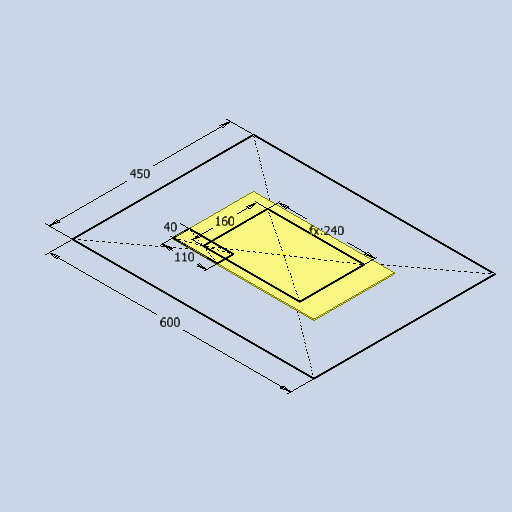
# Autodesk Inventor part: CHASSIS PLATE
Saved by Autodesk Inventor 2026.3 (Build 303398000, 398)
## iProperties
Created: 2026-10-19
Part Number: CHASSIS PLATE
Material: G11 Glass Epoxy Laminate
Document SubType Name: Modeling
Designer: Salim
Density: 18.4985 g/cm^3
Appearance: FIBER
Mass: 3884.68 g
Surface Area: 1433 cm^2
Volume: 210 cm^3
Author: Salim
Autodesk Inventor part; units mm, degrees
ref_plane "YZ Plane" through (0, 0, 0) normal (1, 0, 0) x (0, 1, 0)
ref_plane "XZ Plane" through (0, 0, 0) normal (0, 1, 0) x (-1, 0, 0)
ref_plane "XY Plane" through (0, 0, 0) normal (0, 0, 1) x (1, 0, 0)
sketch "Sketch1" plane through (0, 0, 0) normal (0, 1, 0) x (-1, 0, 0)
  line L0 (-300, -225) -> (300, -225)
  line L1 (300, -225) -> (300, 225)
  line L2 (300, 225) -> (-300, 225)
  line L3 (-300, 225) -> (-300, -225)
  line L4 (-300, -225) -> (300, 225) construction
  line L5 (300, -225) -> (-300, 225) construction
  point P0 (0, 0)
  dimension "d0" = 600
  dimension "d1" = 450
  constraints: 12 end point, 2 midpoint, 2 parallel, 1 horizontal, 1 perpendicular
  measures "d0" distance of L2.end L1.end
  measures "d1" distance of L1.end L0.end
sketch "Sketch2" plane through (0, 0, 0) normal (0, 1, 0) x (-1, 0, 0)
  line L0 (-175, -100) -> (175, -100)
  line L1 (175, -100) -> (175, 100)
  line L2 (175, 100) -> (-175, 100)
  line L3 (-175, 100) -> (-175, -100)
  line L4 (-175, -100) -> (175, 100) construction
  line L5 (175, -100) -> (-175, 100) construction
  point P0 (0, 0)
  dimension "d4" = 350
  dimension "d5" = 200
  constraints: 12 end point, 2 midpoint, 2 parallel, 1 horizontal, 1 perpendicular
  measures "d4" distance of L2.end L1.end
  measures "d5" distance of L1.end L0.end
extrude "Extrusion1" add sketch "Sketch2" along normal blind 3
sketch "Sketch3" plane through (0, 3, 0) normal (0, 1, 0) x (1, 0, 0)
  line L0 (120, -80) -> (-120, -80)
  line L1 (-120, -80) -> (-120, 80)
  line L2 (-120, 80) -> (120, 80)
  line L3 (120, 80) -> (120, -80)
  line L4 (120, -80) -> (-120, 80) construction
  line L5 (-120, -80) -> (120, 80) construction
  line L6 (-65, -60) -> (-175, -60)
  line L7 (-175, -60) -> (-175, -100)
  line L8 (-175, -100) -> (-65, -100)
  line L9 (-65, -100) -> (-65, -60)
  line L10 (-65, -60) -> (-175, -100) construction
  line L11 (-175, -60) -> (-65, -100) construction
  point P0 (0, 0)
  dimension "d8" = 240
  dimension "d9" = 160
  dimension "d10" = 110
  dimension "d11" = 40
  constraints: 24 end point, 4 midpoint, 4 parallel, 2 horizontal, 2 perpendicular
  measures "d8" distance of L1.end L2.end
  measures "d9" distance of L0.end L1.end
  measures "d10" distance of L8.end L7.end
  measures "d11" distance of L7.end L6.end
equation "\"d8\" = 1.5 * d9"
body "Solid1"
